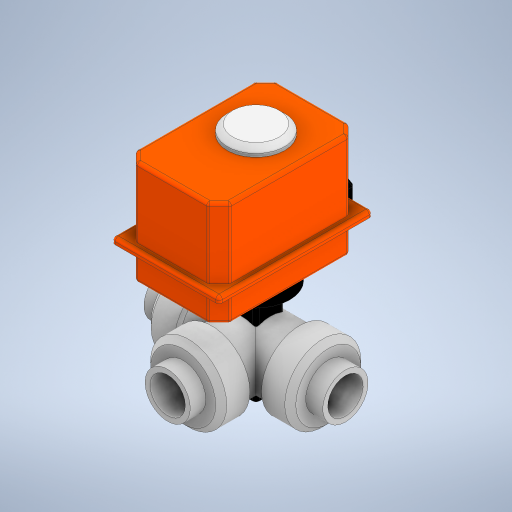
# Autodesk Inventor part: СДР 080 Электроклапан
Saved by Autodesk Inventor 2024.2 (Build 282272000, 272)
## iProperties
Created: 2024-04-05
Part Number: СДР 080 Электроклапан
Material: Generic
Document SubType Name: Modeling
Designer: pokla
Density: 1 g/cm^3
Appearance: Default
Author: pokla
Autodesk Inventor part; units mm, degrees
ref_plane "YZ Plane" through (0, 0, 0) normal (1, 0, 0) x (0, 1, 0)
ref_plane "XZ Plane" through (0, 0, 0) normal (0, 1, 0) x (-1, 0, 0)
ref_plane "XY Plane" through (0, 0, 0) normal (0, 0, 1) x (1, 0, 0)
sketch "Sketch1" plane through (0, 0, 0) normal (0, 1, 0) x (-1, 0, 0)
  line L0 (42.5, -51) -> (-42.5, -51)
  line L1 (-42.5, -51) -> (-42.5, 76)
  line L2 (-42.5, 76) -> (42.5, 76)
  line L3 (42.5, 76) -> (42.5, -51)
  line L4 (-48.5, -57) -> (48.5, -57)
  line L5 (48.5, -57) -> (48.5, 82)
  line L6 (48.5, 82) -> (-48.5, 82)
  line L7 (-48.5, 82) -> (-48.5, -57)
  point P0 (0, 0)
  point P1 (0, -51)
  dimension "d0" = 85
  dimension "d1" = 127
  dimension "d5" = 51
  dimension "d6" = 6
  constraints: 16 end point, 4 parallel, 2 perpendicular, 1 horizontal, 1 midpoint, 1 vertical alignment, 3 other
  measures "d0" distance of L1.end L2.end
  measures "d1" distance of L0.end L1.end
  measures "d5" distance of point (0, 0) point (0, -51)
  measures "d6" distance between parallel lines of L0 L4
extrude "Extrusion1" add sketch "Sketch1" along normal mid plane 5.5 contours L0 L1 L2 L3 | L7 L6 L5 L4
sketch "Sketch2" plane through (0, 0, 0) normal (0, 1, 0) x (-1, 0, 0)
  line L0 (48.5, -57) -> (48.5, 82) projected
  line L1 (48.5, 82) -> (-48.5, 82) projected
  line L2 (-48.5, 82) -> (-48.5, -57) projected
  line L3 (-48.5, -57) -> (48.5, -57) projected
  line L4 (42.5, -51) -> (42.5, 76)
  line L5 (42.5, 76) -> (-42.5, 76)
  line L6 (-42.5, 76) -> (-42.5, -51)
  line L7 (-42.5, -51) -> (42.5, -51)
  point P0 (0, 0)
  dimension "d9" = 6
  constraints: 8 end point, 3 other
  measures "d9" distance between parallel lines of L3 L7
extrude "Extrusion2" add sketch "Sketch2" along normal blind 66 and the other way blind 29 contours L7 L6 L5 L4
sketch "Sketch3" plane through (0, 0, 0) normal (0, 1, 0) x (-1, 0, 0)
  circle A0 centre (0, 0) radius 26
  line L0 (48.5, -57) -> (-48.5, -57) projected
  line L1 (42.5, 76) -> (-42.5, 76) projected
  line L2 (-42.5, 76) -> (-42.5, -51) projected
  line L3 (-42.5, -51) -> (42.5, -51) projected
  line L4 (42.5, -51) -> (42.5, 76) projected
  point P0 (0, 0)
  point P1 (0, -57)
  point P2 (0, -51)
  dimension "d14" = 52
  dimension "d16" = 51
  constraints: 2 midpoint, 1 centre point, 1 coincident
  measures "d14" diameter of A0
  measures "d16" distance of A0.centre point (0, -51)
extrude "Extrusion3" add sketch "Sketch3" along normal blind 74 and the other way blind 0.5 contours A0
sketch "Sketch4" plane through (0, 0, 0) normal (0, 1, 0) x (-1, 0, 0)
  line L0 (27, -27) -> (-27, -27)
  line L1 (-27, -27) -> (-27, 27)
  line L2 (-27, 27) -> (27, 27)
  line L3 (27, 27) -> (27, -27)
  line L4 (42.5, 76) -> (-42.5, 76) projected
  line L5 (-42.5, 76) -> (-42.5, -51) projected
  line L6 (-42.5, -51) -> (42.5, -51) projected
  line L7 (42.5, -51) -> (42.5, 76) projected
  point P0 (0, 0)
  point P1 (0, -27)
  point P2 (0, -51)
  dimension "d21" = 54
  dimension "d22" = 54
  dimension "d23" = 24
  constraints: 8 end point, 2 midpoint, 2 parallel, 1 horizontal, 1 perpendicular, 1 vertical alignment
  measures "d21" distance of L1.end L2.end
  measures "d22" distance of L0.end L1.end
  measures "d23" distance of point (0, -27) point (0, -51)
extrude "Extrusion4" add sketch "Sketch4" against normal blind 39 contours L0 L1 L2 L3
sketch "Sketch6" plane through (0, 0, 0) normal (0, 1, 0) x (-1, 0, 0)
  line L0 (26, 26) -> (26, -26) projected
  line L1 (26, -26) -> (-26, -26) projected
  line L2 (-26, -26) -> (-26, 26) projected
  line L3 (-26, 26) -> (26, 26) projected
  line L4 (-13, -13) -> (13, -13)
  line L5 (13, -13) -> (13, 13)
  line L6 (13, 13) -> (-13, 13)
  line L7 (-13, 13) -> (-13, -13)
  point P0 (0, 0)
  dimension "d29" = 13
  constraints: 8 end point, 3 other
  measures "d29" distance between parallel lines of L1 L4
extrude "Extrusion6" add sketch "Sketch6" against normal blind 132 contours L7 L6 L5 L4
sketch "Sketch7" plane through (0, 0, 0) normal (1, 0, 0) x (0, 1, 0)
  line L0 (-39, -13) -> (-132, -13) projected
  line L1 (-132, 13) -> (-132, -13) projected
  line L2 (-39, 13) -> (-132, 13) projected
  circle A0 centre (-99, 0) radius 28.5
  line L3 (-39, -13) -> (-39, 13) projected
  line L4 (-29, -27) -> (-29, 27) projected
  line L5 (-29, -27) -> (-39, -27) projected
  line L6 (-39, 27) -> (-39, -27) projected
  line L7 (-29, 27) -> (-39, 27) projected
  point P0 (0, 0)
  point P1 (-39, 0)
  dimension "d32" = 57
  dimension "d83" = 60
  constraints: 1 centre point, 1 horizontal alignment, 1 midpoint
  measures "d32" diameter of A0
  measures "d83" distance of point (-39, 0) A0.centre
extrude "Extrusion7" add sketch "Sketch7" along normal mid plane 79 contours A0 L0 | L0 A0 L2 | L2 A0
sketch "Sketch8" plane through (0, 0, 0) normal (1, 0, 0) x (0, 1, 0)
  circle A0 centre (-99, 0) radius 28.5 projected
  circle A1 centre (-99, 0) radius 16
  circle A2 centre (-99, 0) radius 20.5
  point P0 (0, 0)
  dimension "d36" = 32
  dimension "d37" = 41
  constraints: 2 centre point, 2 coincident
  measures "d36" diameter of A1
  measures "d37" diameter of A2
extrude "Extrusion8" add sketch "Sketch8" along normal mid plane 162 contours A2
sketch "Sketch9" plane through (-39.5, -99, 0) normal (-1, 0, 0) x (0, 0, 1)
  circle A0 centre (0, 0) radius 16 projected
  circle A1 centre (0, 0) radius 34.5
  point P0 (0, 99)
  dimension "d40" = 69
  constraints: 1 centre point, 1 coincident
  measures "d40" diameter of A1
extrude "Extrusion9" add sketch "Sketch9" along normal blind 26
chamfer "Chamfer1" distance 5 angle 45 1 edges at (-65.5, -99, -34.5)
mirror "Mirror1" about plane through (0, 0, 0) normal (1, 0, 0) of "Extrusion9", "Chamfer1"
sketch "Sketch10" plane through (0, 0, 0) normal (0, 0, 1) x (1, 0, 0)
  line L0 (-48.5, -2.75) -> (48.5, -2.75) projected
  arc A0 (-12, -14.75) -> (12, -14.75) centre (0, -14.75) ccw
  line L1 (42.5, 66) -> (-42.5, 66) projected
  line L2 (-42.5, 2.75) -> (42.5, 2.75) projected
  line L3 (42.5, 2.75) -> (42.5, 66) projected
  line L4 (-42.5, 2.75) -> (-42.5, 66) projected
  line L5 (12, -14.75) -> (12, -2.75)
  line L6 (-12, -14.75) -> (-12, -2.75)
  point P0 (0, 0)
  point P1 (0, -26.75)
  point P2 (0, -2.75)
  dimension "d47" = 24
  dimension "d72" = 12
  constraints: 4 end point, 3 point on circle, 2 perpendicular, 2 point on line, 2 tangent, 1 centre point, 1 midpoint, 1 vertical alignment
  measures "d47" distance of point (0, -2.75) point (0, -26.75)
  measures "d72" radius of A0
extrude "Extrusion10" add sketch "Sketch10" against normal blind 56 contours L0 L5 A0 L6
sketch "Sketch11" plane through (0, 0, 0) normal (0, 0, 1) x (1, 0, 0)
  arc A0 (-12, -14.75) -> (12, -14.75) centre (0, -14.75) ccw projected
  line L0 (0, -2.6256) -> (10.5, -8.6878)
  line L1 (10.5, -8.6878) -> (10.5, -20.8122)
  line L2 (10.5, -20.8122) -> (0, -26.8744)
  line L3 (0, -26.8744) -> (-10.5, -20.8122)
  line L4 (-10.5, -20.8122) -> (-10.5, -8.6878)
  line L5 (-10.5, -8.6878) -> (0, -2.6256)
  line L6 (12, -2.75) -> (12, -14.75) projected
  line L7 (-12, -14.75) -> (-12, -2.75) projected
  line L8 (12, -2.75) -> (-12, -2.75) projected
  point P0 (0, 0)
  point P1 (0, -14.75)
  dimension "d50" = 21
  constraints: 12 end point, 1 coincident, 13 other
  measures "d50" distance between parallel lines of L4 L1
extrude "Extrusion11" add sketch "Sketch11" against normal blind 82 contours L4 L5 L8 L0 L1 A0 L2 L3 | A0 L3 L4 | L5 L0 L8 | A0 L2 L3 | A0 L1 L2
chamfer "Chamfer2" distance 5 angle 45 6 edges at (-5.25, -5.6567, -82) (5.25, -5.6567, -82) (10.5, -14.75, -82) (5.25, -23.8433, -82) (-5.25, -23.8433, -82) (-10.5, -14.75, -82)
chamfer "Chamfer3" distance 5 angle 45 1 edges at (26, 74, 0)
chamfer "Chamfer4" distance 10 angle 45 8 edges at (42.5, 34.375, 76) (42.5, 34.375, -51) (42.5, -15.875, -51) (42.5, -15.875, 76) (-42.5, -15.875, -51) (-42.5, 34.375, -51) (-42.5, -15.875, 76) (-42.5, 34.375, 76)
fillet "Fillet1" radius 3 32 edges at (-42.5, 66, 12.5) (0, 66, -51) (0, 66, 76) (42.5, 66, 12.5) (-37.5, 66, 71) (37.5, 66, 71) (37.5, 66, -46) (-37.5, 66, -46) (-37.5, -29, 71) (0, -29, 76) (37.5, -29, 71) (42.5, -29, 12.5) (37.5, -29, -46) (0, -29, -51) (-37.5, -29, -46) (-42.5, -29, 12.5) (32.5, 34.375, -51) (42.5, 34.375, -41) (32.5, -15.875, -51) (42.5, -15.875, -41) (-32.5, 34.375, -51) (-42.5, 34.375, -41) (-42.5, -15.875, -41) (-32.5, -15.875, -51) (-32.5, 34.375, 76) (-42.5, 34.375, 66) (-32.5, -15.875, 76) (-42.5, -15.875, 66) (42.5, 34.375, 66) (32.5, 34.375, 76) (42.5, -15.875, 66) (32.5, -15.875, 76)
fillet "Fillet2" radius 3 8 edges at (-48.5, 0, -57) (0, 2.75, -57) (-48.5, 2.75, 12.5) (48.5, 0, -57) (48.5, 2.75, 12.5) (48.5, 0, 82) (0, 2.75, 82) (-48.5, 0, 82)
fillet "Fillet3" radius 3 12 edges at (27, -34, -27) (-27, -34, -27) (-27, -34, 27) (27, -34, 27) (13, -56.3188, 13) (13, -128.1812, 13) (13, -56.3188, -13) (13, -128.1812, -13) (-13, -56.3188, -13) (-13, -128.1812, -13) (-13, -56.3188, 13) (-13, -128.1812, 13)
sketch "Sketch13" plane through (0, 0, 0) normal (0, 1, 0) x (-1, 0, 0)
  line L0 (-31.2574, 76) -> (31.2574, 76) projected
  line L1 (42.5, 64.7574) -> (42.5, -39.7574) projected
  circle A0 centre (6.5, 43) radius 4
  circle A1 centre (6.5, 43) radius 2.5
  point P0 (0, 0)
  dimension "d73" = 8
  dimension "d74" = 33
  dimension "d75" = 36
  dimension "d76" = 5
  constraints: 2 centre point, 1 coincident
  measures "d73" diameter of A0
  measures "d74" distance from line of L0 A0.centre
  measures "d75" distance from line of L1 A0.centre
  measures "d76" diameter of A1
extrude "Extrusion13" add sketch "Sketch13" against normal blind 39
sketch "Sketch14" plane through (0, -39, 0) normal (0, -1, 0) x (1, 0, 0)
  circle A0 centre (0, 0) radius 30.5
  dimension "d80" = 61
  constraints: 1 centre point, 1 coincident
  measures "d80" diameter of A0
extrude "Extrusion14" add sketch "Sketch14" along normal blind 10
sketch "Sketch15" plane through (0, 0, 0) normal (0, 0, 1) x (1, 0, 0)
  line L0 (-10, -73.6376) -> (10, -73.6376) projected
  line L1 (10, -124.3624) -> (-10, -124.3624) projected
  line L2 (39.5, -64.5) -> (39.5, -133.5) projected
  line L3 (-39.5, -64.5) -> (-39.5, -133.5) projected
  circle A0 centre (0, -99) radius 28.5
  line L4 (-39.5, -99) -> (39.5, -99) construction
  point P0 (0, 0)
  dimension "d84" = 57
  constraints: 3 midpoint, 2 end point, 1 centre point, 1 coincident, 1 horizontal alignment
  measures "d84" diameter of A0
extrude "Extrusion15" add sketch "Sketch15" along normal blind 40
sketch "Sketch16" plane through (0, 0, 0) normal (0, 0, 1) x (1, 0, 0)
  circle A0 centre (0, -99) radius 28.5 projected
  circle A1 centre (0, -99) radius 16
  circle A2 centre (0, -99) radius 20.5
  point P0 (0, 0)
  dimension "d87" = 32
  dimension "d88" = 41
  constraints: 2 centre point, 2 coincident
  measures "d87" diameter of A1
  measures "d88" diameter of A2
extrude "Extrusion16" add sketch "Sketch16" along normal blind 80 contours A2
sketch "Sketch17" plane through (0, -99, 40) normal (0, 0, 1) x (1, 0, 0)
  circle A0 centre (0, 0) radius 16 projected
  circle A1 centre (0, 0) radius 34.5
  point P0 (0, 99)
  dimension "d91" = 69
  constraints: 1 centre point, 1 coincident
  measures "d91" diameter of A1
extrude "Extrusion17" add sketch "Sketch17" along normal blind 26
chamfer "Chamfer5" distance 5 angle 45 1 edges at (-34.5, -99, 66)
body "Solid1"
